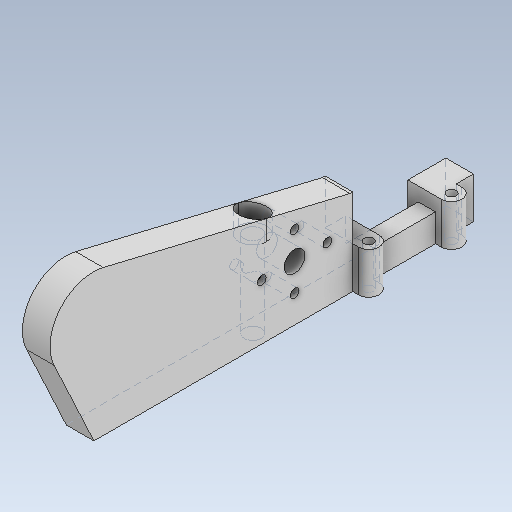
# Autodesk Inventor part: Waffenhalterung_links
Saved by Autodesk Inventor 2026.4 (Build 304435030, 435C)
## iProperties
Created: 2026-11-17
Part Number: Waffenhalterung_links
Material: Generisch
Document SubType Name: Modeling
Designer: weira
Density: 1 g/cm^3
Appearance: Vorgabe
Author: weira
Autodesk Inventor part; units mm, degrees
ref_plane "YZ Plane" through (0, 0, 0) normal (1, 0, 0) x (0, 1, 0)
ref_plane "XZ Plane" through (0, 0, 0) normal (0, 1, 0) x (-1, 0, 0)
ref_plane "XY Plane" through (0, 0, 0) normal (0, 0, 1) x (1, 0, 0)
sketch "Skizze1" plane through (0, 0, 0) normal (1, 0, 0) x (0, 1, 0)
  line L0 (0, 0) -> (100, 0)
  line L1 (100, 0) -> (100, 25)
  line L2 (100, 25) -> (0, 25)
  line L3 (0, 25) -> (0, 0)
  circle A0 centre (0, 30) radius 30
  line L4 (0, 30) -> (13.9892, 0)
  line L5 (0, 30) -> (13.9892, 0) construction
  line L6 (-11.3288, 24.7173) -> (2.6604, -5.2827)
  line L7 (25.3181, 5.2827) -> (11.3288, 35.2827)
  arc A1 (11.3288, 35.2827) -> (-11.3288, 24.7173) centre (0, 30) ccw
  arc A2 (2.6604, -5.2827) -> (25.3181, 5.2827) centre (13.9892, 0) ccw
  point P0 (6.9946, 15)
  point P1 (16.1238, 25)
  point P2 (0.197, 0)
  dimension "d0" = 25
  dimension "d1" = 100
  dimension "d2" = 30
  dimension "d3" = 60
  dimension "d4" = 25
  dimension "d5" = 25
  dimension "d8" = 25
  constraints: 18 end point, 4 equal length, 4 point on circle, 4 tangent, 3 centre point, 1 horizontal, 1 midpoint, 1 perpendicular, 1 point on line
  measures "d0" distance between parallel lines of L0 L2
  measures "d1" distance between parallel lines of L3 L1
  measures "d2" distance of L0.start L4.start
  measures "d3" diameter of A0
  measures "d4" angle of L3 L4
  measures "d5" diameter of A2
  measures "d8" distance between parallel lines of L7 L6
extrude "Extrusion1" add sketch "Skizze1" along normal blind 8 contours A0 L4 L0 | L6 L3 L2 L4 A0 | L6 A1 L7 L2 L3 | L4 A0 L7 A2 L0 | L4 L2 L7 A0 | A0 L7 L2 | L2 L1 L0 A2 L7 A0
sketch "Skizze2" plane through (8, 0, 0) normal (1, 0, 0) x (0, 0, -1)
  arc A0 (-35.2827, 11.3288) -> (-24.7173, -11.3288) centre (-30, 0) ccw projected
  line L0 (-24.7173, -11.3288) -> (0, 0.197) projected
  line L1 (0, 0.197) -> (0, 100) projected
  line L2 (0, 100) -> (-25, 100) projected
  line L3 (-25, 100) -> (-25, 16.1238) projected
  line L4 (-25, 16.1238) -> (-35.2827, 11.3288) projected
  line L5 (-30, 0) -> (-16, 58.3438) construction
  line L6 (-17.845, -2.9167) -> (-3.845, 55.4271)
  line L7 (-28.155, 61.2605) -> (-42.155, 2.9167)
  arc A1 (-42.155, 2.9167) -> (-17.845, -2.9167) centre (-30, 0) ccw
  arc A2 (-3.845, 55.4271) -> (-28.155, 61.2605) centre (-16, 58.3438) ccw
  line L8 (-30.2673, 52.4577) -> (-24.4175, 76.836)
  point P0 (0, 0)
  point P1 (-23, 29.1719)
  point P2 (-25, 34.9183)
  point P3 (-42.155, 2.9167)
  point P4 (-25, 67.0185)
  point P5 (-24.7173, -11.3288)
  point P6 (-24.7173, -11.3288)
  point P7 (0, 64.9861)
  point P8 (0, 28.4754)
  point P9 (-25, 74.4085)
  dimension "d11" = 60
  dimension "d12" = 9
  constraints: 10 end point, 4 point on circle, 4 tangent, 2 centre point, 2 point on line, 1 concentric, 1 midpoint, 1 parallel
  measures "d11" distance of L5.start L5.end
  measures "d12" distance from line of L5.end L3
extrude "Extrusion2" add sketch "Skizze2" against normal blind 8 contours L4 L3 A2 L6 A1 A0 | A0 L7 A2 L3 L4 | A2 L8 L3
sketch "Skizze3" plane through (8, 0, 0) normal (1, 0, 0) x (0, 0, -1)
  arc A0 (-42.155, 2.9167) -> (-24.7173, -11.3288) centre (-30, 0) ccw projected
  line L0 (-24.7173, -11.3288) -> (0, 0.197) projected
  line L1 (0, 0.197) -> (0, 100) projected
  line L2 (0, 100) -> (-25, 100) projected
  line L3 (-25, 100) -> (-25, 74.4085) projected
  line L4 (-30, 0) -> (-16, 58.3438)
  arc A1 (5.3164, 143.2397) -> (5.3164, 153.1217) centre (-5.5643, 148.1807) ccw
  line L5 (5.3164, 153.1217) -> (5.113, 152.9183)
  arc A2 (-0.8267, 158.858) -> (5.113, 152.9183) centre (2.1432, 155.8881) ccw
  line L6 (-0.8267, 158.858) -> (-0.6233, 159.0614)
  arc A3 (-0.6233, 159.0614) -> (-10.5053, 159.0614) centre (-5.5643, 148.1807) ccw
  line L7 (-10.5053, 159.0614) -> (-10.3019, 158.858)
  arc A4 (-16.2416, 152.9183) -> (-10.3019, 158.858) centre (-13.2717, 155.8881) ccw
  line L8 (-16.2416, 152.9183) -> (-16.445, 153.1217)
  arc A5 (-16.445, 153.1217) -> (-16.445, 143.2397) centre (-5.5643, 148.1807) ccw
  line L9 (-16.445, 143.2397) -> (-16.2416, 143.4431)
  arc A6 (-10.3019, 137.5034) -> (-16.2416, 143.4431) centre (-13.2717, 140.4732) ccw
  line L10 (-10.3019, 137.5034) -> (-10.5053, 137.3)
  arc A7 (-10.5053, 137.3) -> (-0.6233, 137.3) centre (-5.5643, 148.1807) ccw
  line L11 (-0.6233, 137.3) -> (-0.8267, 137.5034)
  arc A8 (5.113, 143.4431) -> (-0.8267, 137.5034) centre (2.1432, 140.4732) ccw
  line L12 (5.113, 143.4431) -> (5.3164, 143.2397)
  circle A9 centre (-5.5643, 138.6807) radius 1.25
  circle A10 centre (2.4357, 148.1807) radius 1.25
  circle A11 centre (-5.5643, 157.6807) radius 1.25
  circle A12 centre (-13.5643, 148.1807) radius 1.25
  circle A13 centre (-5.5643, 148.1807) radius 4.25
  circle A14 centre (-5.5643, 148.1807) radius 1.1964
  arc A15 (-5.1193, 53.4028) -> (-5.1193, 63.2848) centre (-16, 58.3438) ccw
  line L13 (-5.1193, 63.2848) -> (-5.3227, 63.0814)
  arc A16 (-11.2624, 69.0211) -> (-5.3227, 63.0814) centre (-8.2925, 66.0513) ccw
  line L14 (-11.2624, 69.0211) -> (-11.059, 69.2245)
  arc A17 (-11.059, 69.2245) -> (-20.941, 69.2245) centre (-16, 58.3438) ccw
  line L15 (-20.941, 69.2245) -> (-20.7376, 69.0211)
  arc A18 (-26.6773, 63.0814) -> (-20.7376, 69.0211) centre (-23.7075, 66.0513) ccw
  line L16 (-26.6773, 63.0814) -> (-26.8807, 63.2848)
  arc A19 (-26.8807, 63.2848) -> (-26.8807, 53.4028) centre (-16, 58.3438) ccw
  line L17 (-26.8807, 53.4028) -> (-26.6773, 53.6062)
  arc A20 (-20.7376, 47.6665) -> (-26.6773, 53.6062) centre (-23.7075, 50.6363) ccw
  line L18 (-20.7376, 47.6665) -> (-20.941, 47.4631)
  arc A21 (-20.941, 47.4631) -> (-11.059, 47.4631) centre (-16, 58.3438) ccw
  line L19 (-11.059, 47.4631) -> (-11.2624, 47.6665)
  arc A22 (-5.3227, 53.6062) -> (-11.2624, 47.6665) centre (-8.2925, 50.6363) ccw
  line L20 (-5.3227, 53.6062) -> (-5.1193, 53.4028)
  circle A23 centre (-16, 48.8438) radius 1.25
  circle A24 centre (-8, 58.3438) radius 1.25
  circle A25 centre (-16, 67.8438) radius 1.25
  circle A26 centre (-24, 58.3438) radius 1.25
  circle A27 centre (-16, 58.3438) radius 4.25
  circle A28 centre (-16, 58.3438) radius 1.1964
  line L21 (-25, 74.4085) -> (-42.155, 2.9167) projected
  point P0 (0, 0)
  point P1 (40.733, 125.8894)
  point P2 (30.2973, 36.0525)
  dimension "d13" = 60
  dimension "d14" = 16
  dimension "d15" = 25
  constraints: 34 end point, 32 point on circle, 28 centre point
  measures "d13" distance of L4.start L4.end
  measures "d14" distance from line of L1 L4.end
  measures "d15" distance of L1.end L2.end
extrude "Extrusion3" cut sketch "Skizze3" against normal through all contours A23 | A24 | A25 | A26
sketch "Skizze4" plane through (0, 100, 25) normal (0, 1, 0) x (1, 0, 0)
  line L0 (8, 0) -> (8, -17.155) projected
  line L1 (0, 0) -> (8, 0) projected
  line L2 (0, -17.155) -> (0, 0) projected
  line L3 (0, -17.155) -> (8, -17.155) projected
  line L4 (0, 25) -> (0, 0) projected
  line L5 (0, 0) -> (8, 0) projected
  line L6 (8, 25) -> (8, 0) projected
  line L7 (0, 25) -> (8, 25) projected
extrude "Extrusion4" add sketch "Skizze4" along normal blind 10.197 contours L1 L4 L7 L6
sketch "Skizze5" plane through (8, 0, 0) normal (1, 0, 0) x (0, 0, -1)
  circle A0 centre (-8, 58.3438) radius 1.25 projected
  circle A1 centre (-16, 48.8438) radius 1.25 projected
  circle A2 centre (-16, 67.8438) radius 1.25 projected
  circle A3 centre (-24, 58.3438) radius 1.25 projected
  arc A4 (-42.155, 2.9167) -> (-24.7173, -11.3288) centre (-30, 0) ccw projected
  line L0 (-24.7173, -11.3288) -> (0, 0.197) projected
  line L1 (0, 0.197) -> (0, 110.197) projected
  line L2 (-25, 110.197) -> (0, 110.197) projected
  line L3 (-25, 74.4085) -> (-25, 110.197) projected
  line L4 (-25, 74.4085) -> (-42.155, 2.9167) projected
  line L5 (-24, 58.3438) -> (-8, 58.3438) construction
  line L6 (-16, 48.8438) -> (-16, 67.8438) construction
  circle A5 centre (-16, 58.3438) radius 3
  point P0 (0, 0)
  dimension "d20" = 6
  constraints: 4 end point, 1 centre point, 1 horizontal, 1 midpoint, 1 vertical
  measures "d20" diameter of A5
extrude "Extrusion5" cut sketch "Skizze5" against normal through all contours A5
sketch "Skizze6" plane through (0, 74.4085, 25) normal (0, 0, 1) x (1, 0, 0)
  line L0 (0, 35.7885) -> (8, 35.7885) projected
  line L1 (0, 35.7885) -> (50.6175, 35.7885)
  line L2 (50.6175, 35.7885) -> (50.6175, 0.7885)
  line L3 (50.6175, 0.7885) -> (0, 0.7885)
  line L4 (0, 0.7885) -> (0, 35.7885)
  point P0 (0, -74.4085)
  dimension "d23" = 35
  constraints: 8 end point, 2 parallel, 1 horizontal, 1 perpendicular
  measures "d23" distance between parallel lines of L3 L1
extrude "Extrusion6" cut sketch "Skizze6" against normal blind 13
sketch "Skizze7" plane through (0, 74.4085, 12) normal (0, 0, 1) x (1, 0, 0)
  circle A0 centre (9.651, 3.7885) radius 1.35
  line L0 (0, 0.7885) -> (0, 35.7885) projected
  line L1 (8, 0.7885) -> (0, 0.7885) projected
  circle A1 centre (9.651, 27.7885) radius 1.35
  circle A2 centre (9.651, 3.7885) radius 3
  circle A3 centre (9.651, 27.7885) radius 3
  line L2 (9.651, 24.7885) -> (8, 24.7885)
  line L3 (8, 35.7885) -> (8, 0.7885) projected
  line L4 (9.651, 30.7885) -> (8, 30.7885)
  line L5 (9.651, 6.7885) -> (8, 6.7885)
  line L6 (9.651, 0.7885) -> (3.0743, 0.7885)
  point P0 (0, -74.4085)
  point P1 (8, 1.2837)
  point P2 (8, 6.2933)
  dimension "d26" = 9.651
  dimension "d27" = 3
  dimension "d28" = 24
  dimension "d29" = 9.651
  dimension "d30" = 6
  dimension "d31" = 2.7
  dimension "d32" = 2.7
  constraints: 8 end point, 4 centre point, 4 point on circle, 4 point on line, 4 tangent, 3 horizontal, 2 coincident
  measures "d26" distance from line of L0 A0.centre
  measures "d27" distance from line of L1 A0.centre
  measures "d28" distance of A0.centre A1.centre
  measures "d29" distance from line of L0 A1.centre
  measures "d30" diameter of A3
  measures "d31" diameter of A1
  measures "d32" diameter of A0
extrude "Extrusion7" add sketch "Skizze7" against normal up to surface (12 mm away) contours A2 L3 | L3 A3 L2 | A2 L3 L5 | L6 L3 A2 | L3 A2 | A3 L3 | L3 L4 A3 picked at (8.1003, 27.7885)
sketch "Skizze8" plane through (0, 74.4085, 12) normal (0, 0, 1) x (1, 0, 0)
  circle A0 centre (9.651, 3.7885) radius 1.35 projected
  circle A1 centre (9.651, 27.7885) radius 1.35 projected
  line L0 (8, 24.7885) -> (8, 6.7885) projected
  line L1 (8, 24.7885) -> (9.651, 24.7885) projected
  arc A2 (9.651, 24.7885) -> (9.651, 30.7885) centre (9.651, 27.7885) ccw projected
  line L2 (9.651, 30.7885) -> (8, 30.7885) projected
  line L3 (8, 35.7885) -> (8, 30.7885) projected
  line L4 (0, 35.7885) -> (8, 35.7885) projected
  line L5 (0, 0.7885) -> (0, 35.7885) projected
  line L6 (8, 0.7885) -> (0, 0.7885) projected
  line L7 (8, 0.7885) -> (9.651, 0.7885) projected
  arc A3 (9.651, 0.7885) -> (9.651, 6.7885) centre (9.651, 3.7885) ccw projected
  line L8 (9.651, 6.7885) -> (8, 6.7885) projected
  line L9 (8, 24.7885) -> (0, 24.7885)
  line L10 (0, 24.7885) -> (0, 6.7885)
  line L11 (0, 6.7885) -> (8, 6.7885)
  line L12 (8, 6.7885) -> (8, 24.7885)
  point P0 (0, -74.4085)
  point P1 (0, 24.7885)
  constraints: 8 end point, 2 parallel, 1 horizontal, 1 perpendicular, 1 point on line
extrude "Extrusion8" cut sketch "Skizze8" against normal blind 4 contours L0 L11 L5 L9
chamfer "Fasen1" distance 3 angle 45 1 edges at (0, 90.197, 8)
sketch "Skizze9" plane through (0, 74.4085, 25) normal (0, 0, 1) x (1, 0, 0)
  line L0 (0, 35.7885) -> (8, 35.7885) projected
  line L1 (8, 0) -> (8, -71.4918) projected
  line L2 (0, -71.4918) -> (0, 0) projected
  circle A0 centre (4, -24.2115) radius 4
  point P0 (0, -74.4085)
  point P1 (4, 35.7885)
  dimension "d40" = 60
  dimension "d41" = 8
  constraints: 1 centre point, 1 midpoint
  measures "d40" distance of point (4, 35.788) A0.centre
  measures "d41" diameter of A0
extrude "Extrusion9" cut sketch "Skizze9" along normal blind 10
hole "Bohrung1" at (4, 50.197, 25) direction (0, 0, -1) diameter 5 end through all
sketch "Skizze10" plane through (0, 74.4085, 25) normal (0, 0, 1) x (1, 0, 0)
  point P0 (0, -74.4085)
equation "\"d2\" = 0.5 * d3"
equation "\"d29\" = d26"
